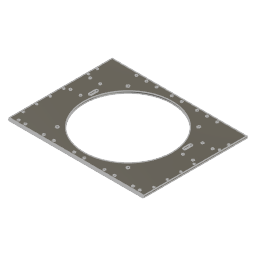
Top-Panel-3mm (Autodesk Fusion 360 design; units mm, degrees)
part number: 2026-04-19-09-19-55-662
Autodesk Fusion 360 part; units mm, degrees
sketch "Sketch1" plane through (0, 0, 0) normal (0, 0, 1) x (1, 0, 0)
  line L0 (100, 87.5) -> (-100, 87.5)
  circle A0 centre (52.5, 62.5) radius 2
  circle A1 centre (52.5, -42.5) radius 2
  circle A2 centre (-52.5, 62.5) radius 2
  line L1 (100, -67.5) -> (-100, -67.5)
  circle A3 centre (-52.5, -42.5) radius 2
  line L2 (100, -67.5) -> (100, 87.5)
  line L3 (-100, -67.5) -> (-100, 87.5)
  line L4 (-95, -67.5) -> (-95, 87.5)
  line L5 (95, -67.5) -> (95, 87.5)
  circle A4 centre (-97, -48.5) radius 1.35
  circle A5 centre (-97, -28.5) radius 1.35
  circle A6 centre (-97, -8.5) radius 1.35
  circle A7 centre (-97, 11.5) radius 1.35
  circle A8 centre (-97.5, 48.5) radius 1.35
  circle A9 centre (-97.5, 61.85) radius 1.35
  circle A10 centre (97.5, 61.85) radius 1.35
  circle A11 centre (97.5, 48.5) radius 1.35
  circle A12 centre (97, 11.5) radius 1.35
  circle A13 centre (97, -8.5) radius 1.35
  circle A14 centre (97, -28.5) radius 1.35
  circle A15 centre (97, -48.5) radius 1.35
  circle A16 centre (0, 10) radius 65.5
  circle A17 centre (7.5, 82.5) radius 1.6
  circle A18 centre (-7.5, 82.5) radius 1.6
  circle A19 centre (-30, 82.5) radius 1.6
  circle A20 centre (-45, 82.5) radius 1.6
  circle A21 centre (-60, 82.5) radius 1.6
  circle A22 centre (30, 82.5) radius 1.6
  circle A23 centre (45, 82.5) radius 1.6
  circle A24 centre (60, 82.5) radius 1.6
  circle A25 centre (-7.5, -62.5) radius 1.6
  circle A26 centre (7.5, -62.5) radius 1.6
  circle A27 centre (52.5, -62.5) radius 1.6
  circle A28 centre (37.5, -62.5) radius 1.6
  circle A29 centre (-37.5, -62.5) radius 1.6
  circle A30 centre (-52.5, -62.5) radius 1.6
  circle A31 centre (80, -62.5) radius 1.6
  circle A32 centre (-80, -62.5) radius 1.6
  circle A33 centre (-90, -62.5) radius 1.6
  circle A34 centre (90, -62.5) radius 1.6
  circle A35 centre (76, 44.75) radius 1.6
  circle A36 centre (91, 44.75) radius 1.6
  circle A37 centre (91, 15.5) radius 1.6
  circle A38 centre (76, 15.5) radius 1.6
  line L6 (91, 44.75) -> (95, 44.75)
  line L7 (76, 44.75) -> (72, 44.75)
  circle A39 centre (-76, 15.5) radius 1.6
  circle A40 centre (-91, 15.5) radius 1.6
  circle A41 centre (-76, 44.75) radius 1.6
  circle A42 centre (-91, 44.75) radius 1.6
  line L8 (-91, 44.75) -> (-95, 44.75)
  line L9 (72, 33.125) -> (72, 24.125)
  line L10 (68, 33.125) -> (68, 24.125)
  arc A43 (72, 33.125) -> (68, 33.125) centre (70, 33.125) ccw
  arc A44 (68, 24.125) -> (72, 24.125) centre (70, 24.125) ccw
  arc A45 (-72, 24.125) -> (-68, 24.125) centre (-70, 24.125) ccw
  line L11 (-72, 33.125) -> (-72, 24.125)
  arc A46 (-68, 33.125) -> (-72, 33.125) centre (-70, 33.125) ccw
  line L12 (-68, 33.125) -> (-68, 24.125)
  dimension "d17" = 131
  dimension "d20" = 3.2
  constraint horizontal L0
  constraint horizontal L1
  constraint perpendicular L0 L3
  constraint coincident L1 L4.start
  constraint coincident L0 L4.end
  constraint perpendicular L0 L4
  constraint coincident L1 L5.start
  constraint coincident L0 L5.end
  constraint perpendicular L0 L5
  constraint equal A18 A19
  constraint equal A18 A20
  constraint equal A18 A21
  constraint equal A18 A24
  constraint equal A18 A23
  constraint equal A18 A22
  constraint equal A17 A18
  constraint coincident A36.centre L6.start
  constraint coincident L5 L6.end
  constraint perpendicular L5 L6
  constraint coincident A35.centre L7.start
  constraint horizontal L7
  constraint coincident A42.centre L8.start
  constraint horizontal L8
  constraint tangent L9 A44
  constraint perpendicular L6 L9
  constraint tangent L10 A44
  constraint perpendicular L6 L10
  constraint tangent A45 L12
  constraint tangent A45 L11
  measures "d17" diameter of A16
  measures "d20" diameter of A18
extrude "Extrude1" add sketch "Sketch1" along normal blind 3
fillet "Fillet1" radius 1 2 edges at (0, -67.5, 3) (0, 87.5, 3)
